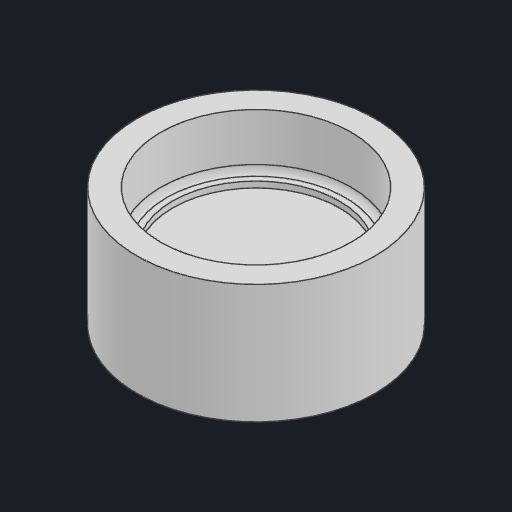
# Autodesk Inventor part: revolve-plain
Saved by Autodesk Inventor 2026.1 (Build 301233000, 233)
## iProperties
Created: 2026-11-04
Part Number: revolve-plain
Material: Generic
Document SubType Name: Modeling
Designer: anony
Density: 1 g/cm^3
Appearance: Default
Author: anony
Autodesk Inventor part; units mm, degrees
ref_plane "YZ Plane" through (0, 0, 0) normal (1, 0, 0) x (0, 1, 0)
ref_plane "XZ Plane" through (0, 0, 0) normal (0, 1, 0) x (-1, 0, 0)
ref_plane "XY Plane" through (0, 0, 0) normal (0, 0, 1) x (1, 0, 0)
sketch "Sketch1" plane through (0, 0, 0) normal (0, 0, 1) x (1, 0, 0)
  line L0 (0, 0) -> (10, 0)
  line L1 (10, 0) -> (10, 10)
  line L2 (10, 10) -> (8, 10)
  line L3 (8, 10) -> (8, 5.5)
  line L4 (8, 5.5) -> (7, 5.5)
  line L5 (7, 5.5) -> (7, 5)
  line L6 (7, 5) -> (0, 5)
  line L7 (0, 5) -> (0, 0)
  line L8 (0, -2) -> (0, 12)
  constraints: 16 end point
revolve "Revolution1" add sketch "Sketch1" angle 360 about axis through (0, -10, 0) along (0, 1, 0)
fillet "Fillet1" radius 0.5 1 edges at (-8, 5.5, 0)
body "Solid1"
